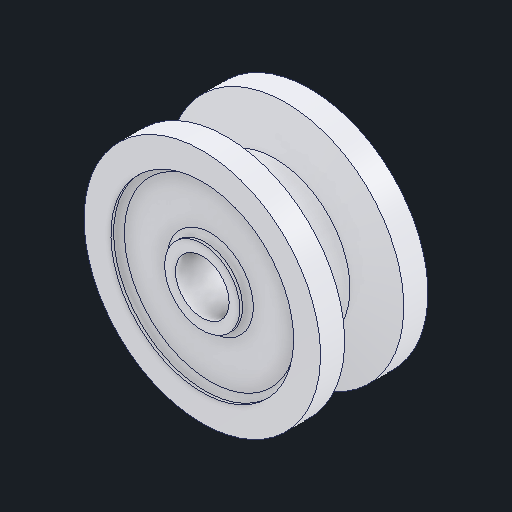
# Autodesk Inventor part: polia
Saved by Autodesk Inventor 2026 (Build 300175000, 175)
## iProperties
Created: 2025-04-24
Part Number: polia
Material: Generic
Document SubType Name: Modeling
Designer: dawac
Density: 1 g/cm^3
Appearance: Default
Author: dawac
Autodesk Inventor part; units mm, degrees
ref_plane "YZ Plane" through (0, 0, 0) normal (1, 0, 0) x (0, 1, 0)
ref_plane "XZ Plane" through (0, 0, 0) normal (0, 1, 0) x (-1, 0, 0)
ref_plane "XY Plane" through (0, 0, 0) normal (0, 0, 1) x (1, 0, 0)
sketch "Sketch1" plane through (0, 0, 0) normal (1, 0, 0) x (0, 1, 0)
  line L0 (0, 37.9401) -> (0, -45.9451)
  line L1 (0, 0) -> (48.856, 0)
  line L2 (5, 0) -> (5, -10)
  line L3 (5, -10) -> (7, -10)
  line L4 (7, -10) -> (7, -9.5)
  line L5 (8, -8.5) -> (16, -8.5)
  line L6 (17, -9.5) -> (17, -10)
  line L7 (17, -10) -> (22, -10)
  line L8 (22, -10) -> (22, -5.5)
  line L9 (22, -5.5) -> (14, -3.5)
  arc A0 (17, -9.5) -> (16, -8.5) centre (16, -9.5) ccw
  arc A1 (8, -8.5) -> (7, -9.5) centre (8, -9.5) ccw
  line L10 (5, 0) -> (5, 10)
  line L11 (5, 10) -> (7, 10)
  line L12 (7, 10) -> (7, 9.5)
  line L13 (8, 8.5) -> (16, 8.5)
  line L14 (17, 9.5) -> (17, 10)
  line L15 (17, 10) -> (22, 10)
  line L16 (22, 10) -> (22, 5.5)
  line L17 (22, 5.5) -> (14, 3.5)
  arc A2 (16, 8.5) -> (17, 9.5) centre (16, 9.5) ccw
  arc A3 (7, 9.5) -> (8, 8.5) centre (8, 9.5) ccw
  line L18 (14, 3.5) -> (10.0142, 0)
  line L19 (14, -3.5) -> (10.0142, 0)
  point P0 (14, 0)
  point P1 (6, -10)
  point P2 (19.5, -10)
  dimension "d0" = 1
  dimension "d2" = 20
  dimension "d3" = 2
  dimension "d5" = 10
  dimension "d6" = 1.5
  dimension "d7" = 5
  dimension "d8" = 11
  dimension "d10" = 7
  dimension "d14" = 20
  dimension "d16" = 8
  dimension "d17" = 5
  constraints: 40 end point, 12 symmetric about line, 8 point on circle, 6 perpendicular, 4 centre point, 4 tangent, 3 point on line, 2 midpoint, 2 vertical, 1 equal radius, 1 horizontal, 2 other
  measures "d0" radius of A0
  measures "d2" distance from line of point (6, -10) L11
  measures "d3" distance of L2.end L3.end
  measures "d5" distance of L3.end L6.end
  measures "d6" distance from line of point (19.5, -10) L5
  measures "d7" distance of L6.end L7.end
  measures "d8" distance of L16.end L8.end
  measures "d10" distance of L9.end L17.end
  measures "d14" distance of L7.end L15.end
  measures "d16" horizontal distance of L17.end L16.end
  measures "d17" distance of L1.start L2.start
revolve "Revolution1" add sketch "Sketch1" angle 360 about axis through (0, 0, 37.9401) along (0, 0, -1)
body "Solid1"
